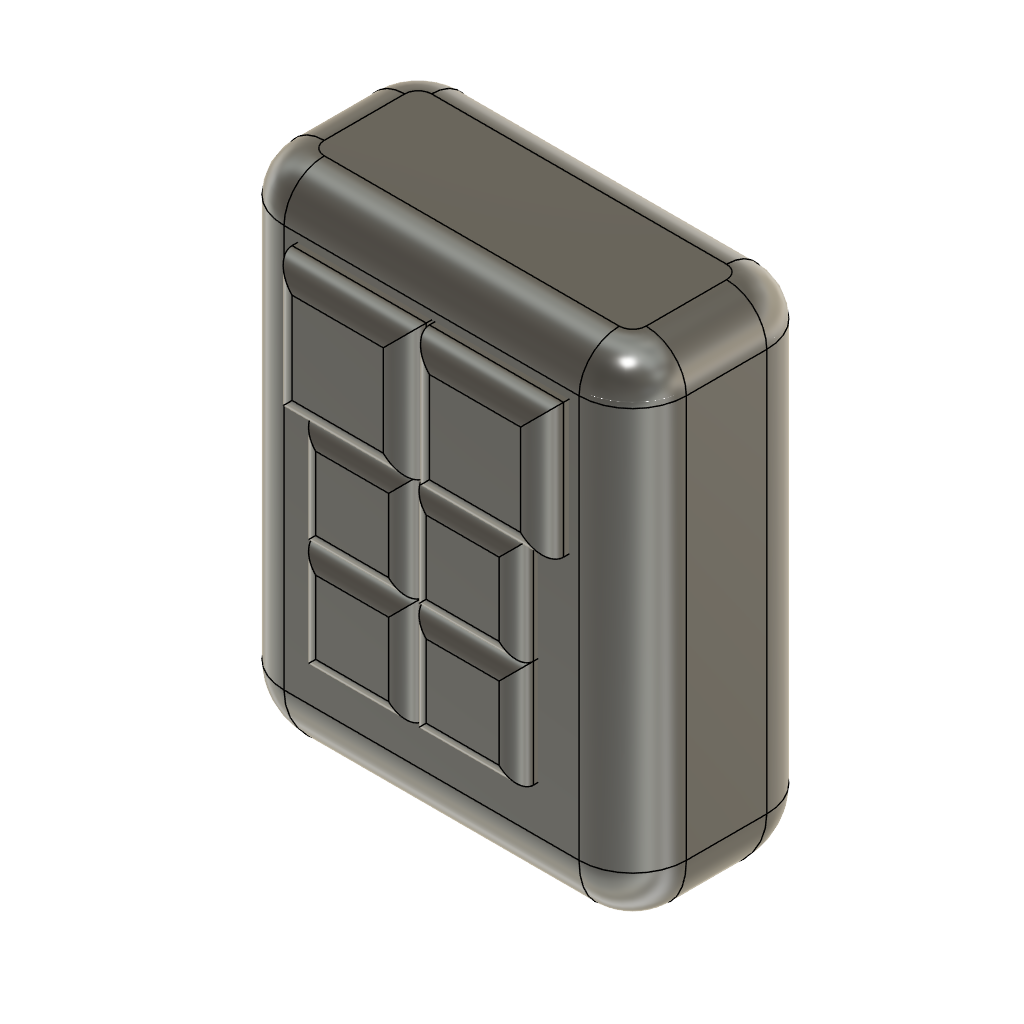
Gerry FULL (Autodesk Fusion 360 archive; units mm, degrees)
design "Monster body"
part number: 2026-09-30-13-02-19-659
Autodesk Fusion 360 part; units mm, degrees
sketch "Sketch1" plane through (0, 0, 0) normal (0, 0, 1) x (1, 0, 0)
  line L0 (25, -25) -> (-50, -25)
  line L1 (-50, -25) -> (-50, 10)
  line L2 (-50, 10) -> (25, 10)
  line L3 (25, 10) -> (25, -25)
  constraint horizontal L0
  constraint vertical L1
  constraint horizontal L2
  constraint vertical L3
extrude "Extrude2" add sketch "Sketch1" along normal blind 95 makes body 1
fillet "Fillet1" radius 10 4 edges at (25, -25, 47.5) (-50, -25, 47.5) (25, 10, 47.5) (-50, 10, 47.5) on bodies 1
fillet "Fillet2" radius 7.5 8 edges at (22.0711, 7.0711, 95) (-12.5, 10, 95) (-47.0711, 7.0711, 95) (-50, -7.5, 95) (-47.0711, -22.0711, 95) (-12.5, -25, 95) (22.0711, -22.0711, 95) (25, -7.5, 95) on bodies 1
fillet "Fillet3" radius 12.5 8 edges at (22.0711, 7.0711, 0) (25, -7.5, 0) (22.0711, -22.0711, 0) (-12.5, -25, 0) (-47.0711, -22.0711, 0) (-50, -7.5, 0) (-47.0711, 7.0711, 0) (-12.5, 10, 0) on bodies 1
sketch "Sketch2" plane through (0, 0, 0) normal (0, 0, 1) x (1, 0, 0)
  line L0 (150, 0) -> (125, 0)
  line L1 (125, 0) -> (125, 25)
  line L2 (125, 25) -> (150, 25)
  line L3 (150, 25) -> (150, 0)
  constraint horizontal L0
  constraint vertical L1
  constraint horizontal L2
  constraint vertical L3
extrude "Extrude3" add sketch "Sketch2" along normal blind 6 separate body makes body 2
fillet "Fillet4" radius 4 4 edges at (137.5, 25, 6) (137.5, 0, 6) (125, 12.5, 6) (150, 12.5, 6) on bodies 2
copy_body "CopyPasteBodies1" bodies 2 makes body 3
move_body "Move1" bodies 3 to x (1, 0, 0) y (0, 1, 0) z (0, 0, 1) at (60, 0, 0)
scale "Scale1" factor 0.8 about (206, 4, 6) bodies 3
move_body "Move2" bodies 2 to x (1, 0, 0) y (0, 0, 1) z (0, -1, 0) at (0, 1, 1)
move_body "Move3" bodies 2 to x (1, 0, 0) y (0, 1, 0) z (0, 0, 1) at (-165, -25, 60)
copy_body "CopyPasteBodies2" bodies 2 makes body 4
move_body "Move4" bodies 4 to x (1, 0, 0) y (0, 1, 0) z (0, 0, 1) at (30, 0, 0)
move_body "Move5" bodies 3 to x (1, 0, 0) y (0, 0, 1) z (0, -1, 0) at (0, 12, -9.6)
move_body "Move6" bodies 3 to x (1, 0, 0) y (0, 1, 0) z (0, 0, 1) at (-225, -35, 50)
copy_body "CopyPasteBodies3" bodies 3 makes body 5
move_body "Move7" bodies 5 to x (1, 0, 0) y (0, 1, 0) z (0, 0, 1) at (25, 0, 0)
copy_body "CopyPasteBodies4" bodies 3 makes body 6
move_body "Move8" bodies 6 to x (1, 0, 0) y (0, 1, 0) z (0, 0, 1) at (0, 0, -20)
copy_body "CopyPasteBodies5" bodies 3 makes body 7
move_body "Move9" bodies 7 to x (1, 0, 0) y (0, 1, 0) z (0, 0, 1) at (25, 0, -20)
move_body "Move10" bodies 2 3 6 to x (1, 0, 0) y (0, 1, 0) z (0, 0, 1) at (2.5, 0, 0)
move_body "Move11" bodies 4 5 7 to x (1, 0, 0) y (0, 1, 0) z (0, 0, 1) at (-1.9, 0, 0)
sketch "Sketch3" plane through (0, 0, 0) normal (0, 0, 1) x (1, 0, 0)
